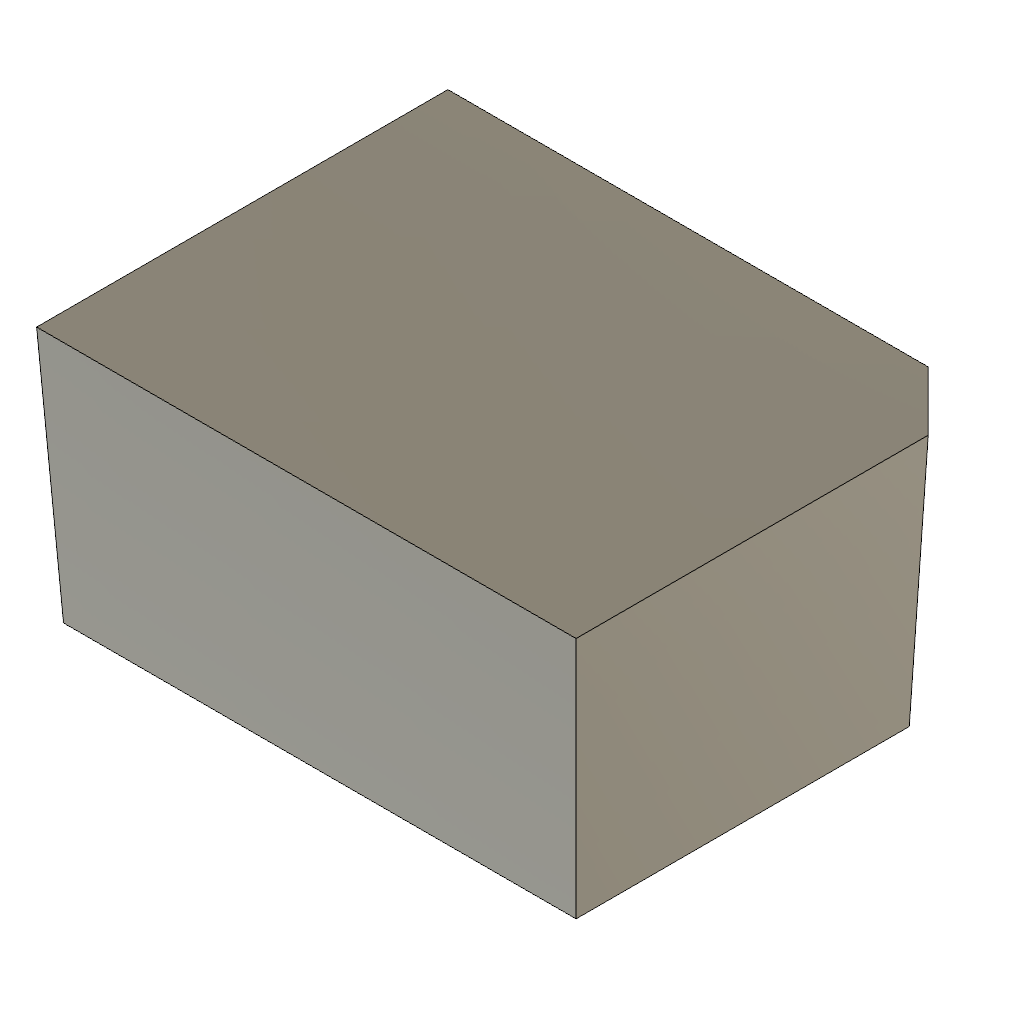
vendor_DraftCutPart (Autodesk Fusion 360 design; units mm, degrees)
Autodesk Fusion 360 part; units mm, degrees
sketch "Base sketch" plane through (0, 0, 0) normal (0, 0, 1) x (1, 0, 0)
  line L0 (0, 0) -> (40, 0)
  line L1 (40, 0) -> (40, 30)
  line L2 (40, 30) -> (0, 30)
  line L3 (0, 30) -> (0, 0)
extrude "Base extrude" add sketch "Base sketch" along normal blind 20
chamfer "Corner cut" distance 4 angle 45 1 edges at (40, 30, 10) tangent chain off
draft "Side draft" angle 3 neutral plane through (0, 0, 0) pull (0, 0, -1) 5 faces at (13.3333, 0, 6.6667) (40, 8.6667, 6.6667) (38.6667, 27.3333, 6.6667) (24, 30, 6.6667) (0, 20, 6.6667)
equation "height = 20.0 mm"
